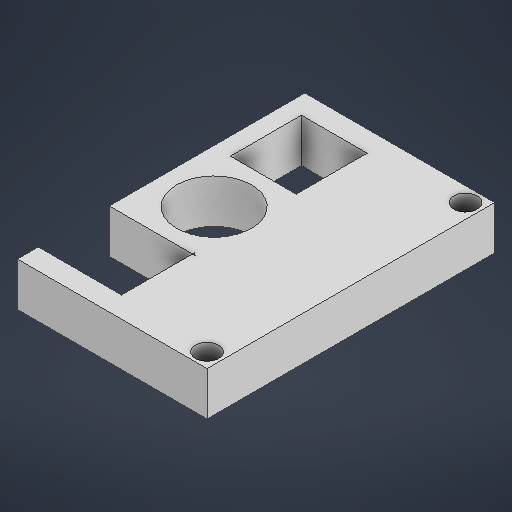
# Autodesk Inventor part: Peça4
Saved by Autodesk Inventor 2026.2 (Build 302298010, 298A)
## iProperties
Created: 2026-08-22
Part Number: Peça4
Material: Genérico
Document SubType Name: Sheet Metal
Designer: Admin
Density: 1 g/cm^3
Sheet Metal Rule: Padrão_mm
Appearance: Padrão
Author: Admin
## iProperties of the stored document Peça4_3DPrint.ipt
Created: 2026-08-22
Part Number: Peça4_3DPrint
Material: Genérico
Document SubType Name: Modeling
Designer: Admin
Density: 1 g/cm^3
Appearance: Padrão
Author: Admin
Autodesk Inventor part; units mm, degrees
ref_plane "YZ Plane" through (0, 0, 0) normal (1, 0, 0) x (0, 1, 0)
ref_plane "XZ Plane" through (0, 0, 0) normal (0, 1, 0) x (-1, 0, 0)
ref_plane "XY Plane" through (0, 0, 0) normal (0, 0, 1) x (1, 0, 0)
sketch "Esboço1" plane through (0, 0, 0) normal (0, 1, 0) x (-1, 0, 0)
  circle A0 centre (0.2093, 0.1565) radius 2.1
  line L0 (0.2093, 0.1565) -> (0.2093, 15.1565)
  circle A1 centre (0.2093, 15.1565) radius 2
  line L1 (0.2093, 0.1565) -> (0.2093, -14.8435)
  circle A2 centre (0.2093, -14.8435) radius 2.1
  line L2 (0.2093, 15.1565) -> (-4.9907, 15.1565)
  line L3 (-4.9907, 15.1565) -> (-4.9907, -14.8435)
  line L4 (-4.9907, -14.8435) -> (0.2093, -14.8435)
  circle A3 centre (0.2093, 0.1565) radius 6.1
  line L5 (0.2093, 24.8565) -> (24.9093, 24.8565)
  line L6 (24.9093, 24.8565) -> (24.9093, 0.1565)
  line L7 (24.9093, 0.1565) -> (0.2093, 0.1565)
  line L8 (0.2093, 0.1565) -> (0.2093, 24.8565)
  line L9 (24.9093, 0.1565) -> (0.2093, 0.1565)
  line L10 (0.2093, 0.1565) -> (0.2093, -24.5435)
  line L11 (0.2093, -24.5435) -> (24.9093, -24.5435)
  line L12 (24.9093, -24.5435) -> (24.9093, 0.1565)
  line L13 (0.2093, -24.5435) -> (-24.4907, -24.5435)
  line L14 (-24.4907, 0.1565) -> (0.2093, 0.1565)
  line L15 (0.2093, 0.1565) -> (0.2093, -24.5435)
  line L16 (0.2093, 24.8565) -> (-24.4907, 24.8565)
  line L17 (-24.4907, 0.1565) -> (0.2093, 0.1565)
  line L18 (0.2093, 0.1565) -> (0.2093, 24.8565)
  line L19 (-4.9907, 15.1565) -> (-4.9907, 24.8565)
  line L20 (-4.9907, -14.8435) -> (-4.9907, -24.5435)
  line L21 (-4.9907, 24.8565) -> (-24.4907, 24.8565)
  line L22 (-24.4907, -24.5435) -> (-4.9907, -24.5435)
  line L23 (-4.9907, -24.5435) -> (-4.9907, 24.8565)
  line L24 (0.2093, -14.8435) -> (0.2093, -20.9435)
  line L25 (0.2093, -20.9435) -> (-4.9907, -20.9435)
  line L26 (0.2093, -14.8435) -> (0.2093, -8.7435)
  line L27 (0.2093, -8.7435) -> (-4.9907, -8.7435)
  line L28 (0.2093, -8.7435) -> (0.2093, -14.8435)
  line L29 (0.2093, 15.1565) -> (0.2093, 9.0565)
  line L30 (0.2093, 15.1565) -> (0.2093, 21.2565)
  line L31 (0.2093, 21.2565) -> (-4.9907, 21.2565)
  line L32 (0.2093, 9.0565) -> (-4.9907, 9.0565)
  line L33 (6.3093, 0.1565) -> (6.3093, -24.5435)
  line L34 (6.3093, 0.1565) -> (6.3093, 24.8565)
  line L35 (-4.9907, 21.2565) -> (6.3093, 21.2565)
  line L36 (6.3093, 21.2565) -> (6.3093, 24.8565)
  line L37 (6.3093, 24.8565) -> (-4.9907, 24.8565)
  line L38 (-4.9907, 24.8565) -> (-4.9907, 21.2565)
  line L39 (-4.9907, -20.9435) -> (6.3093, -20.9435)
  line L40 (6.3093, -20.9435) -> (6.3093, -24.5435)
  line L41 (6.3093, -24.5435) -> (-4.9907, -24.5435)
  line L42 (-4.9907, -24.5435) -> (-4.9907, -20.9435)
  line L43 (6.3093, 21.2565) -> (0.2093, 21.2565)
  line L44 (0.2093, 21.2565) -> (0.2093, 9.0565)
  line L45 (0.2093, 9.0565) -> (6.3093, 9.0565)
  line L46 (6.3093, 9.0565) -> (6.3093, 21.2565)
  line L47 (0.2093, -8.7435) -> (6.3093, -8.7435)
  line L48 (6.3093, -8.7435) -> (6.3093, -20.9435)
  line L49 (6.3093, -20.9435) -> (0.2093, -20.9435)
  line L50 (0.2093, -20.9435) -> (0.2093, -8.7435)
  line L51 (6.3093, -24.5435) -> (9.3093, -24.5435)
  line L52 (9.3093, -24.5435) -> (9.3093, 24.8565)
  line L53 (9.3093, 24.8565) -> (6.3093, 24.8565)
  line L54 (6.3093, 24.8565) -> (6.3093, -24.5435)
  circle A4 centre (0.2093, 0.1565) radius 8.3
  circle A5 centre (0.2093, 15.1565) radius 8.3
  line L55 (-4.9907, -8.7435) -> (-24.4907, -8.7435)
  line L56 (-24.4907, -24.5435) -> (-4.9907, -24.5435)
  line L57 (-4.9907, -24.5435) -> (-4.9907, -8.7435)
  line L58 (-4.9907, 9.0565) -> (-24.4907, 9.0565)
  line L59 (-24.4907, 24.8565) -> (-4.9907, 24.8565)
  line L60 (-4.9907, 24.8565) -> (-4.9907, 9.0565)
  line L61 (-8.0907, 0.1565) -> (-8.0907, -8.7435)
  line L62 (-8.0907, 0.1565) -> (-8.0907, 9.0565)
  line L63 (-8.0907, -8.7435) -> (-8.5907, -8.7435)
  line L64 (-8.5907, -8.7435) -> (-8.5907, 9.0565)
  line L65 (-8.5907, 9.0565) -> (-8.0907, 9.0565)
  line L66 (-8.0907, 9.0565) -> (-8.0907, -8.7435)
  line L67 (-8.5907, -8.7435) -> (-24.4907, -8.7435)
  line L68 (-24.4907, -24.5435) -> (-8.5907, -24.5435)
  line L69 (-8.5907, -24.5435) -> (-8.5907, -8.7435)
  line L70 (-8.5907, -8.7435) -> (-24.4907, -8.7435)
  line L71 (-24.4907, 24.8565) -> (-8.5907, 24.8565)
  line L72 (-8.5907, 24.8565) -> (-8.5907, -8.7435)
  line L73 (9.3093, -24.5435) -> (6.3093, -24.5435)
  line L74 (6.3093, -24.5435) -> (6.3093, -20.9435)
  line L75 (6.3093, -20.9435) -> (9.3093, -20.9435)
  line L76 (9.3093, -20.9435) -> (9.3093, -24.5435)
  line L77 (6.3093, 21.2565) -> (9.3093, 21.2565)
  line L78 (9.3093, 21.2565) -> (9.3093, 24.8565)
  line L79 (9.3093, 24.8565) -> (6.3093, 24.8565)
  line L80 (6.3093, 24.8565) -> (6.3093, 21.2565)
  line L81 (9.3093, 24.8565) -> (9.3093, 23.0565)
  line L82 (-24.4907, -24.5435) -> (-21.4907, -24.5435)
  line L83 (-24.4907, 24.8565) -> (-21.4907, 24.8565)
  line L84 (-24.4907, -24.5435) -> (-19.9907, -24.5435)
  line L85 (-24.4907, 24.8565) -> (-19.9907, 24.8565)
  line L86 (-8.5907, -24.5435) -> (-13.0907, -24.5435)
  line L87 (-13.0907, -24.5435) -> (-13.0907, -20.0435)
  line L88 (-13.0907, -20.0435) -> (-8.5907, -20.0435)
  line L89 (-8.5907, -20.0435) -> (-8.5907, -24.5435)
  line L90 (-8.5907, 24.8565) -> (-13.0907, 24.8565)
  line L91 (-13.0907, 24.8565) -> (-13.0907, 20.3565)
  line L92 (-13.0907, 20.3565) -> (-8.5907, 20.3565)
  line L93 (-8.5907, 20.3565) -> (-8.5907, 24.8565)
  line L94 (-13.0907, -22.2935) -> (-8.5907, -22.2935)
  line L95 (-8.5907, 22.6065) -> (-13.0907, 22.6065)
  circle A6 centre (-10.8407, -22.2935) radius 1.55
  circle A7 centre (-10.8407, 22.6065) radius 1.55
  circle A8 centre (0.2093, 0.1565) radius 6.4
  line L96 (9.3093, 21.2565) -> (6.3093, 21.2565)
  line L97 (6.3093, 21.2565) -> (6.3093, 9.0565)
  line L98 (6.3093, 9.0565) -> (9.3093, 9.0565)
  line L99 (9.3093, 9.0565) -> (9.3093, 21.2565)
  line L100 (6.3093, -8.7435) -> (9.3093, -8.7435)
  line L101 (9.3093, -8.7435) -> (9.3093, -20.9435)
  line L102 (9.3093, -20.9435) -> (6.3093, -20.9435)
  line L103 (6.3093, -20.9435) -> (6.3093, -8.7435)
  line L104 (-24.4907, -24.5435) -> (-19.4907, -24.5435)
  line L105 (-24.4907, -19.5435) -> (-24.4907, -24.5435)
  circle A9 centre (0.2093, 0.1565) radius 6.45
  circle A10 centre (0.2093, 0.1565) radius 24.7
  line L106 (-24.4907, -24.5435) -> (-23.2907, -24.5435)
  line L107 (-23.2907, -24.5435) -> (-23.2907, 24.8565)
  line L108 (-23.2907, 24.8565) -> (-24.4907, 24.8565)
  line L109 (-24.4907, 24.8565) -> (-24.4907, -24.5435)
  line L110 (-23.2907, 24.8565) -> (-18.2907, 24.8565)
  line L111 (-18.2907, 24.8565) -> (-18.2907, 19.8565)
  line L112 (-18.2907, 19.8565) -> (-23.2907, 19.8565)
  line L113 (-23.2907, 19.8565) -> (-23.2907, 24.8565)
  line L114 (-23.2907, -24.5435) -> (-18.2907, -24.5435)
  line L115 (-18.2907, -24.5435) -> (-18.2907, -19.5435)
  line L116 (-18.2907, -19.5435) -> (-23.2907, -19.5435)
  line L117 (-23.2907, -19.5435) -> (-23.2907, -24.5435)
  line L118 (-18.2907, 22.3565) -> (-23.2907, 22.3565)
  line L119 (-18.2907, -22.0435) -> (-23.2907, -22.0435)
  circle A11 centre (-20.7907, 22.3565) radius 2
  circle A12 centre (-20.7907, -22.0435) radius 2
  point P0 (0, 0)
  point P1 (-4.9907, 8.6874)
  point P2 (-5.4192, 9.0565)
  dimension "d6" = 12.2
  dimension "d13" = 16.6
  dimension "d0" = 4.2
  dimension "d1" = 15
  dimension "d2" = 4
  dimension "d3" = 15
  dimension "d4" = 4.2
  dimension "d5" = 5.2
  dimension "d8" = 6.1
  dimension "d9" = 6.1
  dimension "d10" = 6.1
  dimension "d11" = 6.1
  dimension "d12" = 3
  dimension "d14" = 16.6
  dimension "d15" = 0.5
  dimension "d16" = 4.5
  dimension "d17" = 4.5
  dimension "d18" = 4.5
  dimension "d19" = 4.5
  dimension "d20" = 3.1
  dimension "d21" = 3.1
  dimension "d22" = 12.8
  dimension "d29" = 12.9
  dimension "d30" = 49.4
  dimension "d31" = 1.2
  dimension "d32" = 5
  dimension "d33" = 5
  dimension "d34" = 5
  dimension "d35" = 5
  dimension "d36" = 4
  dimension "d37" = 4
  constraints: 240 end point, 42 parallel, 30 horizontal, 27 perpendicular, 22 point on line, 13 midpoint, 11 centre point, 9 coincident, 4 vertical, 2 horizontal alignment, 4 other
  measures "d0" diameter of A0
  measures "d1" distance of L0.start L0.end
  measures "d2" diameter of A1
  measures "d3" distance of L0.start L1.end
  measures "d4" diameter of A2
  measures "d5" distance of L2.start L3.start
  measures "d8" distance of L4.end L24.end
  measures "d9" distance of L4.end L27.start
  measures "d10" distance of L2.start L45.start
  measures "d11" distance of L2.start L30.end
  measures "d12" distance of L54.start L52.end
  measures "d14" diameter of A5
  measures "d15" distance of L64.end L66.start
  measures "d16" distance of L87.end L88.end
  measures "d17" distance of L86.end L87.end
  measures "d18" distance of L93.start L91.end
  measures "d19" distance of L91.end L90.end
  measures "d20" diameter of A6
  measures "d21" diameter of A7
  measures "d22" diameter of A8
  measures "d29" diameter of A9
  measures "d30" diameter of A10
  measures "d31" distance of L108.end L107.end
  measures "d32" distance of L111.end L112.end
  measures "d33" distance of L110.end L111.end
  measures "d34" distance of L116.end L115.end
  measures "d35" distance of L115.end L114.end
  measures "d36" diameter of A11
  measures "d37" diameter of A12
extrude "Extrusão1" add sketch "Esboço1" along normal blind 7.5 contours A9 L34 A4 L7 | L7 A4 L33 A9 | L33 A4 L1 A9 | A9 L0 A5 A4 L34 | A9 L3 A4 A5 L0 | L1 A4 L3 A9 | A4 L34 L98 L52 L7 | L7 L52 L100 L33 A4 | L33 L47 L1 A4 | A4 A5 L45 L34 | A5 A4 L0 | L0 A4 A5 | A9 L14 A4 L3 | L1 L27 L3 A4 | L3 A4 L14 A9 | L100 L52 L75 L33 | A4 L0 L45 A5 | A4 A5 L3 L32 L0 | A4 L3 A5 | A4 L62 L58 A5 L3 | L3 L55 L61 A4 | L75 L52 A10 L33 | L33 A10 L10 L39 | L61 L55 L64 L14 | L14 L64 L58 L62 | L3 L20 A10 L69 L55 | A10 L34 L5 L52 | L52 L77 L34 A10 | L52 L11 L33 A10 | L33 L11 A10 | L10 A10 L20 L25 | L64 L55 A10 L107 L14 | L14 L107 A10 L58 L64 | L58 L72 A10 L19 A5 | L58 A5 L19 L3 | A10 L5 L34 | L34 L35 A5 L8 A10 | L13 L20 A10 | L35 L8 A5 | L69 L88 L87 A10 L55 | L58 A10 L91 L92 L72 | A5 L8 L31 L19 | L19 A10 L8 A5 | A10 L19 L16 | L13 L69 A10 L20 | A10 L55 L107 | L107 L58 A10 | A10 L87 L13 L115 L116 L107 L55 | L69 L94 A6 A10 L87 L88 | L58 L107 L112 L111 L16 L91 A10 | L92 L91 A10 A7 L95 L72 | A10 L72 L16 L19 | L13 L87 L94 A6 A10 L69 | A10 A6 L94 L69 | A10 A6 L94 L87 | L91 L95 A7 A10 | L95 A7 A10 L72 | A10 A7 L95 L91 L16 L72 | A10 L94 A6 | A6 L94 A10 | L116 L115 L119 A12 L107 | L107 L118 A11 L111 L112 | A10 L94 A6 | A6 L94 A10 | A10 L95 A7 | A7 L95 A10 | L95 A10 A7 | A10 L95 A7 | L13 L107 L119 A12 L115 | L16 L111 L118 A11 L107
equation "\"Raio_vergadura\" = Espessura"
equation "\"Largura_alívio_de_vergadura\" = Espessura"
equation "\"Profundidade_alívio_de_vergadura\" = 0.5 * Espessura"
equation "\"Tamanho_alívio_de_dobra\" = 4 * Espessura"
equation "\"Remanescente_mínimo\" = 2 * Espessura"
equation "\"Raiodetransição\" = Raio_vergadura"
equation "\"Tamanho_de_raio_de_Jacobi\" = Raio_vergadura"
equation "\"TamanhoFolga\" = Espessura"
equation "\"Espessura\" = 0.5"
